Autodesk Fusion 360 part; units mm, degrees
(part 6 of 8)
equation "d503 = ( caseWidth - 20 mm ) - bottomBossDiameter / 2 - bottomReliefClearance"
equation "d504 = ( ( ( caseWidth - 20 mm ) - bottomBossDiameter / 2 - bottomReliefClearance ) + ( bottomBossDiameter + 2 * bottomReliefClearance ) ) - ( ( caseWidth - 20 mm ) - bottomBossDiameter / 2 - bottomReliefClearance )"
equation "d505 = ( ( 0 mm ) + ( 4.8 mm + bottomBossDiameter / 2 + bottomReliefClearance ) ) - ( 0 mm )"
equation "d506 = rearHeight + 1 mm"
equation "diffuserSkin = 0.8 mm" comment "Prototype optical front skin"
equation "diffuserSideWall = 1 mm" comment "Prototype hollow plug walls"
equation "diffuserRearDepth = 6 mm" comment "Rear rim presses strip edges"
equation "ledTrayDepth = 6.2 mm" comment "LED strip seat below exterior face"
equation "ledTrayThickness = 2.4 mm" comment "Structural LED tray"
equation "ledWireWidth = 4 mm" comment "Right-hand prototype wiring relief"
equation "oledBoardWidth = 36 mm" comment "Measured PCB orientation across case"
equation "oledBoardLength = 34 mm" comment "Measured PCB orientation along face"
equation "oledPcbThickness = 1.6 mm" comment "Confirmed OLED PCB thickness"
equation "oledPcbFrontDepth = 2.8 mm" comment "Provisional OLED PCB front seating depth"
equation "oledFitClearance = 0.2 mm" comment "Prototype PCB fit clearance"
equation "oledBackDepth = oledPcbFrontDepth + oledPcbThickness" comment "OLED PCB rear face"
equation "pcbPostDiameter = 4.4 mm" comment "Trial PCB screw support diameter"
equation "pcbPostHeight = pcbRailHeight + pcbRailThickness - pcbMountHeight" comment "Short PCB posts below control hardware"
equation "pcbPostPilot = 1.7 mm" comment "Trial M2 plastic thread pilot; coupon required"
equation "d523 = -( shellWall + diffuserFlangeThickness )"
equation "d525 = ( caseWidth - ledWidth ) / 2 + diffuserClearance - diffuserFlange"
equation "d526 = ( ledCenter - ledHeight / 2 + diffuserClearance - diffuserFlange ) + faceOriginV"
equation "d527 = ( ( ( caseWidth - ledWidth ) / 2 + diffuserClearance - diffuserFlange ) + ( ledWidth - 2 * diffuserClearance + 2 * diffuserFlange ) ) - ( ( caseWidth - ledWidth ) / 2 + diffuserClearance - diffuserFlange )"
equation "d528 = ( ( ( ledCenter - ledHeight / 2 + diffuserClearance - diffuserFlange ) + faceOriginV ) + ( ledHeight - 2 * diffuserClearance + 2 * diffuserFlange ) ) - ( ( ledCenter - ledHeight / 2 + diffuserClearance - diffuserFlange ) + faceOriginV )"
equation "d529 = -( diffuserRearDepth - shellWall - diffuserFlangeThickness )"
equation "d531 = -diffuserSkin"
equation "d533 = ( caseWidth - ledWidth ) / 2 + diffuserClearance + diffuserSideWall"
equation "d534 = ( ledCenter - ledHeight / 2 + diffuserClearance + diffuserSideWall ) + faceOriginV"
equation "d535 = ( ( ( caseWidth - ledWidth ) / 2 + diffuserClearance + diffuserSideWall ) + ( ledWidth - 2 * ( diffuserClearance + diffuserSideWall ) ) ) - ( ( caseWidth - ledWidth ) / 2 + diffuserClearance + diffuserSideWall )"
equation "d536 = ( ( ( ledCenter - ledHeight / 2 + diffuserClearance + diffuserSideWall ) + faceOriginV ) + ( ledHeight - 2 * ( diffuserClearance + diffuserSideWall ) ) ) - ( ( ledCenter - ledHeight / 2 + diffuserClearance + diffuserSideWall ) + faceOriginV )"
equation "d537 = -( diffuserRearDepth + 1 mm )"
equation "d539 = ( caseWidth + ledWidth ) / 2 - diffuserSideWall - 1 mm"
equation "d540 = ( ledCenter - ledWireWidth / 2 ) + faceOriginV"
equation "d541 = ( ( ( caseWidth + ledWidth ) / 2 - diffuserSideWall - 1 mm ) + ( 5 mm ) ) - ( ( caseWidth + ledWidth ) / 2 - diffuserSideWall - 1 mm )"
equation "d542 = ( ( ( ledCenter - ledWireWidth / 2 ) + faceOriginV ) + ( ledWireWidth ) ) - ( ( ledCenter - ledWireWidth / 2 ) + faceOriginV )"
equation "d543 = -( diffuserRearDepth )"
equation "d545 = ( caseWidth - ledWidth ) / 2 + diffuserClearance - diffuserFlange - flangePocketClearance"
equation "d546 = ( ledCenter - ledHeight / 2 + diffuserClearance - diffuserFlange - flangePocketClearance ) + faceOriginV"
equation "d547 = ( ( ( caseWidth - ledWidth ) / 2 + diffuserClearance - diffuserFlange - flangePocketClearance ) + ( ledWidth - 2 * diffuserClearance + 2 * ( diffuserFlange + flangePocketClearance ) ) ) - ( ( caseWidth - ledWidth ) / 2 + diffuserClearance - diffuserFlange - flangePocketClearance )"
equation "d548 = ( ( ( ledCenter - ledHeight / 2 + diffuserClearance - diffuserFlange - flangePocketClearance ) + faceOriginV ) + ( ledHeight - 2 * diffuserClearance + 2 * ( diffuserFlange + flangePocketClearance ) ) ) - ( ( ledCenter - ledHeight / 2 + diffuserClearance - diffuserFlange - flangePocketClearance ) + faceOriginV )"
equation "d549 = -( diffuserRearDepth - shellWall - carrierClearance + 0.2 mm )"
equation "d551 = ( caseWidth - ledWidth ) / 2 - 0.2 mm"
equation "d552 = ( faceLength - ( shellWall + carrierClearance ) / cos(caseTilt) - ( shellWall + carrierClearance + carrierThickness ) * tan(caseTilt) - carrierRim + 0.4 mm ) + faceOriginV"
equation "d553 = ( ( ( caseWidth - ledWidth ) / 2 - 0.2 mm ) + ( ledWidth + 0.4 mm ) ) - ( ( caseWidth - ledWidth ) / 2 - 0.2 mm )"
equation "d554 = ( ( ( faceLength - ( shellWall + carrierClearance ) / cos(caseTilt) - ( shellWall + carrierClearance + carrierThickness ) * tan(caseTilt) - carrierRim + 0.4 mm ) + faceOriginV ) + ( 4 mm ) ) - ( ( faceLength - ( shellWall + carrierClearance ) / cos(caseTilt) - ( shellWall + carrierClearance + carrierThickness ) * tan(caseTilt) - carrierRim + 0.4 mm ) + faceOriginV )"
equation "d555 = -( ledTrayDepth + ledTrayThickness - shellWall - carrierClearance )"
equation "d557 = -ledTrayDepth"
equation "d559 = ( caseWidth - ledWidth ) / 2 - 0.2 mm"
equation "d560 = ( ledCenter - ledHeight / 2 - 0.2 mm ) + faceOriginV"
equation "d561 = ( ( ( caseWidth - ledWidth ) / 2 - 0.2 mm ) + ( ledWidth + 0.4 mm ) ) - ( ( caseWidth - ledWidth ) / 2 - 0.2 mm )"
equation "d562 = ( ( ( ledCenter - ledHeight / 2 - 0.2 mm ) + faceOriginV ) + ( ( faceLength - ( shellWall + carrierClearance ) / cos(caseTilt) - ( ledTrayDepth + ledTrayThickness ) * tan(caseTilt) ) - ( ledCenter - ledHeight / 2 - 0.2 mm ) ) ) - ( ( ledCenter - ledHeight / 2 - 0.2 mm ) + faceOriginV )"
equation "d563 = -( ledTrayThickness )"
equation "d565 = ( caseWidth + ledWidth ) / 2 - 2 mm"
equation "d566 = ( ledCenter - ledWireWidth / 2 ) + faceOriginV"
equation "d567 = ( ( ( caseWidth + ledWidth ) / 2 - 2 mm ) + ( 4 mm ) ) - ( ( caseWidth + ledWidth ) / 2 - 2 mm )"
equation "d568 = ( ( ( ledCenter - ledWireWidth / 2 ) + faceOriginV ) + ( ledWireWidth ) ) - ( ( ledCenter - ledWireWidth / 2 ) + faceOriginV )"
equation "d569 = -( ledTrayThickness + 1 mm )"
equation "d571 = layoutGap + ( displayWidth - oledBoardWidth ) / 2"
equation "d572 = ( controlCenter - oledBoardLength / 2 ) + faceOriginV"
equation "d573 = ( ( layoutGap + ( displayWidth - oledBoardWidth ) / 2 ) + ( oledBoardWidth ) ) - ( layoutGap + ( displayWidth - oledBoardWidth ) / 2 )"
equation "d574 = ( ( ( controlCenter - oledBoardLength / 2 ) + faceOriginV ) + ( 3 mm ) ) - ( ( controlCenter - oledBoardLength / 2 ) + faceOriginV )"
equation "d575 = -( oledPcbFrontDepth )"
equation "d577 = layoutGap + ( displayWidth - oledBoardWidth ) / 2"
equation "d578 = ( controlCenter + oledBoardLength / 2 - 5 mm ) + faceOriginV"
equation "d579 = ( ( layoutGap + ( displayWidth - oledBoardWidth ) / 2 ) + ( oledBoardWidth ) ) - ( layoutGap + ( displayWidth - oledBoardWidth ) / 2 )"
equation "d580 = ( ( ( controlCenter + oledBoardLength / 2 - 5 mm ) + faceOriginV ) + ( 3 mm ) ) - ( ( controlCenter + oledBoardLength / 2 - 5 mm ) + faceOriginV )"
equation "d581 = -( oledPcbFrontDepth )"
equation "d583 = layoutGap + ( displayWidth - oledBoardWidth ) / 2 - oledFitClearance"
equation "d584 = ( controlCenter - oledBoardLength / 2 - oledFitClearance ) + faceOriginV"
equation "d585 = ( ( layoutGap + ( displayWidth - oledBoardWidth ) / 2 - oledFitClearance ) + ( oledBoardWidth + 2 * oledFitClearance ) ) - ( layoutGap + ( displayWidth - oledBoardWidth ) / 2 - oledFitClearance )"
equation "d586 = ( ( ( controlCenter - oledBoardLength / 2 - oledFitClearance ) + faceOriginV ) + ( oledBoardLength + 2 * oledFitClearance ) ) - ( ( controlCenter - oledBoardLength / 2 - oledFitClearance ) + faceOriginV )"
equation "d587 = -( oledBackDepth + oledFitClearance - shellWall - carrierClearance )"
equation "d589 = -( oledBackDepth + oledFitClearance )"
equation "d592 = ( controlCenter - 18 mm ) + faceOriginV"
equation "d593 = ( ( 18 mm ) + ( 14 mm ) ) - ( 18 mm )"
equation "d594 = ( ( ( controlCenter - 18 mm ) + faceOriginV ) + ( 1 mm ) ) - ( ( controlCenter - 18 mm ) + faceOriginV )"
equation "d595 = -( oledBackDepth + oledFitClearance + 2 mm - shellWall - carrierClearance )"
equation "d598 = ( controlCenter - 18 mm ) + faceOriginV"
equation "d599 = ( ( 18 mm ) + ( 14 mm ) ) - ( 18 mm )"
equation "d600 = ( ( ( controlCenter - 18 mm ) + faceOriginV ) + ( 4 mm ) ) - ( ( controlCenter - 18 mm ) + faceOriginV )"
equation "d601 = -( 2 mm )"
equation "d604 = ( controlCenter + 12.8 mm ) + faceOriginV"
equation "d605 = ( ( 18 mm ) + ( 14 mm ) ) - ( 18 mm )"
equation "d606 = ( ( ( controlCenter + 12.8 mm ) + faceOriginV ) + ( 3.8 mm ) ) - ( ( controlCenter + 12.8 mm ) + faceOriginV )"
equation "d607 = -( ledTrayThickness )"
equation "d610 = ( controlCenter + 13 mm ) + faceOriginV"
equation "d611 = ( ( 18 mm ) + ( 14 mm ) ) - ( 18 mm )"
equation "d612 = ( ( ( controlCenter + 13 mm ) + faceOriginV ) + ( 2 mm ) ) - ( ( controlCenter + 13 mm ) + faceOriginV )"
equation "d613 = -( 2 mm )"
equation "d615 = layoutGap + ( displayWidth - oledBoardWidth ) / 2 - oledFitClearance"
equation "d616 = ( controlCenter - oledBoardLength / 2 - oledFitClearance ) + faceOriginV"
equation "d617 = ( ( layoutGap + ( displayWidth - oledBoardWidth ) / 2 - oledFitClearance ) + ( oledBoardWidth + 2 * oledFitClearance ) ) - ( layoutGap + ( displayWidth - oledBoardWidth ) / 2 - oledFitClearance )"
equation "d618 = ( ( ( controlCenter - oledBoardLength / 2 - oledFitClearance ) + faceOriginV ) + ( oledBoardLength + 2 * oledFitClearance ) ) - ( ( controlCenter - oledBoardLength / 2 - oledFitClearance ) + faceOriginV )"
equation "d619 = -( oledBackDepth + oledFitClearance - shellWall - carrierClearance )"
equation "d621 = pcbTopHeight + 4 mm"
equation "d624 = ( pcbFront + ( pcbLength - pcbHolePitchY ) / 2 + 0 * pcbHolePitchY ) - 2 mm"
equation "d625 = ( ( 3.2 mm ) + ( 1.6 mm ) ) - ( 3.2 mm )"
equation "d626 = ( ( ( pcbFront + ( pcbLength - pcbHolePitchY ) / 2 + 0 * pcbHolePitchY ) - 2 mm ) + ( 4 mm ) ) - ( ( pcbFront + ( pcbLength - pcbHolePitchY ) / 2 + 0 * pcbHolePitchY ) - 2 mm )"
equation "d630 = ( pcbFront + ( pcbLength - pcbHolePitchY ) / 2 + 0 * pcbHolePitchY ) - 2 mm"
equation "d631 = ( ( 3.2 mm ) + ( 3.8 mm ) ) - ( 3.2 mm )"
equation "d632 = ( ( ( pcbFront + ( pcbLength - pcbHolePitchY ) / 2 + 0 * pcbHolePitchY ) - 2 mm ) + ( 4 mm ) ) - ( ( pcbFront + ( pcbLength - pcbHolePitchY ) / 2 + 0 * pcbHolePitchY ) - 2 mm )"
equation "d635 = pcbLeft + ( pcbWidth - pcbHolePitchX ) / 2 + 0 * pcbHolePitchX"
equation "d636 = pcbFront + ( pcbLength - pcbHolePitchY ) / 2 + 0 * pcbHolePitchY"
equation "d637 = pcbPostDiameter"
equation "d640 = pcbLeft + ( pcbWidth - pcbHolePitchX ) / 2 + 0 * pcbHolePitchX"
equation "d641 = pcbFront + ( pcbLength - pcbHolePitchY ) / 2 + 0 * pcbHolePitchY"
equation "d642 = pcbPostPilot"
equation "d645 = caseWidth - 4.8 mm"
equation "d646 = ( pcbFront + ( pcbLength - pcbHolePitchY ) / 2 + 0 * pcbHolePitchY ) - 2 mm"
equation "d647 = ( ( caseWidth - 4.8 mm ) + ( 1.6 mm ) ) - ( caseWidth - 4.8 mm )"
equation "d648 = ( ( ( pcbFront + ( pcbLength - pcbHolePitchY ) / 2 + 0 * pcbHolePitchY ) - 2 mm ) + ( 4 mm ) ) - ( ( pcbFront + ( pcbLength - pcbHolePitchY ) / 2 + 0 * pcbHolePitchY ) - 2 mm )"
equation "d651 = caseWidth - 7 mm"
equation "d652 = ( pcbFront + ( pcbLength - pcbHolePitchY ) / 2 + 0 * pcbHolePitchY ) - 2 mm"
equation "d653 = ( ( caseWidth - 7 mm ) + ( 3.8 mm ) ) - ( caseWidth - 7 mm )"
equation "d654 = ( ( ( pcbFront + ( pcbLength - pcbHolePitchY ) / 2 + 0 * pcbHolePitchY ) - 2 mm ) + ( 4 mm ) ) - ( ( pcbFront + ( pcbLength - pcbHolePitchY ) / 2 + 0 * pcbHolePitchY ) - 2 mm )"
equation "d657 = pcbLeft + ( pcbWidth - pcbHolePitchX ) / 2 + 1 * pcbHolePitchX"
equation "d658 = pcbFront + ( pcbLength - pcbHolePitchY ) / 2 + 0 * pcbHolePitchY"
equation "d659 = pcbPostDiameter"
equation "d662 = pcbLeft + ( pcbWidth - pcbHolePitchX ) / 2 + 1 * pcbHolePitchX"
equation "d663 = pcbFront + ( pcbLength - pcbHolePitchY ) / 2 + 0 * pcbHolePitchY"
equation "d664 = pcbPostPilot"
equation "d668 = ( pcbFront + ( pcbLength - pcbHolePitchY ) / 2 + 1 * pcbHolePitchY ) - 2 mm"
equation "d669 = ( ( 3.2 mm ) + ( 1.6 mm ) ) - ( 3.2 mm )"
equation "d670 = ( ( ( pcbFront + ( pcbLength - pcbHolePitchY ) / 2 + 1 * pcbHolePitchY ) - 2 mm ) + ( 4 mm ) ) - ( ( pcbFront + ( pcbLength - pcbHolePitchY ) / 2 + 1 * pcbHolePitchY ) - 2 mm )"
equation "d674 = ( pcbFront + ( pcbLength - pcbHolePitchY ) / 2 + 1 * pcbHolePitchY ) - 2 mm"
equation "d675 = ( ( 3.2 mm ) + ( 3.8 mm ) ) - ( 3.2 mm )"
equation "d676 = ( ( ( pcbFront + ( pcbLength - pcbHolePitchY ) / 2 + 1 * pcbHolePitchY ) - 2 mm ) + ( 4 mm ) ) - ( ( pcbFront + ( pcbLength - pcbHolePitchY ) / 2 + 1 * pcbHolePitchY ) - 2 mm )"
equation "d679 = pcbLeft + ( pcbWidth - pcbHolePitchX ) / 2 + 0 * pcbHolePitchX"
equation "d680 = pcbFront + ( pcbLength - pcbHolePitchY ) / 2 + 1 * pcbHolePitchY"
equation "d681 = pcbPostDiameter"
equation "d684 = pcbLeft + ( pcbWidth - pcbHolePitchX ) / 2 + 0 * pcbHolePitchX"
equation "d685 = pcbFront + ( pcbLength - pcbHolePitchY ) / 2 + 1 * pcbHolePitchY"
equation "d686 = pcbPostPilot"
equation "d689 = caseWidth - 4.8 mm"
equation "d690 = ( pcbFront + ( pcbLength - pcbHolePitchY ) / 2 + 1 * pcbHolePitchY ) - 2 mm"
equation "d691 = ( ( caseWidth - 4.8 mm ) + ( 1.6 mm ) ) - ( caseWidth - 4.8 mm )"
equation "d692 = ( ( ( pcbFront + ( pcbLength - pcbHolePitchY ) / 2 + 1 * pcbHolePitchY ) - 2 mm ) + ( 4 mm ) ) - ( ( pcbFront + ( pcbLength - pcbHolePitchY ) / 2 + 1 * pcbHolePitchY ) - 2 mm )"
equation "d695 = caseWidth - 7 mm"
equation "d696 = ( pcbFront + ( pcbLength - pcbHolePitchY ) / 2 + 1 * pcbHolePitchY ) - 2 mm"
equation "d697 = ( ( caseWidth - 7 mm ) + ( 3.8 mm ) ) - ( caseWidth - 7 mm )"
equation "d698 = ( ( ( pcbFront + ( pcbLength - pcbHolePitchY ) / 2 + 1 * pcbHolePitchY ) - 2 mm ) + ( 4 mm ) ) - ( ( pcbFront + ( pcbLength - pcbHolePitchY ) / 2 + 1 * pcbHolePitchY ) - 2 mm )"
equation "d701 = pcbLeft + ( pcbWidth - pcbHolePitchX ) / 2 + 1 * pcbHolePitchX"
equation "d702 = pcbFront + ( pcbLength - pcbHolePitchY ) / 2 + 1 * pcbHolePitchY"
equation "d703 = pcbPostDiameter"
equation "d706 = pcbLeft + ( pcbWidth - pcbHolePitchX ) / 2 + 1 * pcbHolePitchX"
equation "d707 = pcbFront + ( pcbLength - pcbHolePitchY ) / 2 + 1 * pcbHolePitchY"
equation "d708 = pcbPostPilot"
equation "d711 = -( carrierBossDepth + carrierClearance )"
equation "d713 = mountSideX"
equation "d714 = ( mountFrontV ) + faceOriginV"
equation "d715 = mountBossDiameter"
equation "d716 = -( carrierClearance )"
equation "d718 = mountSideX"
equation "d719 = ( mountFrontV ) + faceOriginV"
equation "d720 = insertPilotDiameter"
equation "d721 = carrierClearance + 0.1 mm"
equation "d723 = caseWidth - mountSideX"
equation "d724 = ( mountFrontV ) + faceOriginV"
equation "d725 = mountBossDiameter"
equation "d726 = -( carrierClearance )"
equation "d728 = caseWidth - mountSideX"
equation "d729 = ( mountFrontV ) + faceOriginV"
equation "d730 = insertPilotDiameter"
equation "d731 = carrierClearance + 0.1 mm"
equation "d733 = mountSideX"
equation "d734 = ( mountRearV ) + faceOriginV"
equation "d735 = mountBossDiameter"
equation "d736 = -( carrierClearance )"
equation "d738 = mountSideX"
equation "d739 = ( mountRearV ) + faceOriginV"
equation "d740 = insertPilotDiameter"
equation "d741 = carrierClearance + 0.1 mm"
equation "d743 = mountSideX"
equation "d744 = ( mountRearV ) + faceOriginV"
equation "d745 = mountBossDiameter + 2 * mountPocketClearance"
equation "d746 = carrierBossDepth + carrierClearance"
equation "d748 = mountSideX"
equation "d749 = ( mountRearV ) + faceOriginV"
equation "d750 = m2Clearance"
equation "d751 = -( carrierPadDepth )"
equation "d754 = caseLength - 3 mm"
equation "d755 = bottomBossDiameter + 2 * bottomReliefClearance"
equation "d756 = rearHeight + 1 mm"
equation "d758 = caseWidth - mountSideX"
equation "d759 = ( mountRearV ) + faceOriginV"
equation "d760 = mountBossDiameter"
equation "d761 = -( carrierClearance )"
equation "d763 = caseWidth - mountSideX"
equation "d764 = ( mountRearV ) + faceOriginV"
equation "d765 = insertPilotDiameter"
equation "d766 = carrierClearance + 0.1 mm"
equation "d768 = caseWidth - mountSideX"
equation "d769 = ( mountRearV ) + faceOriginV"
equation "d770 = mountBossDiameter + 2 * mountPocketClearance"
equation "d771 = carrierBossDepth + carrierClearance"
equation "d773 = caseWidth - mountSideX"
equation "d774 = ( mountRearV ) + faceOriginV"
equation "d775 = m2Clearance"
equation "d776 = -( carrierPadDepth )"
equation "d778 = caseWidth - 20 mm"
equation "d779 = caseLength - 3 mm"
equation "d780 = bottomBossDiameter + 2 * bottomReliefClearance"
equation "d781 = rearHeight + 1 mm"
equation "pcbMountHeight = 22.3 mm" comment "Upper solder-side PCB seating face; components face bottom cover"
equation "pcbRailHeight = 27.8 mm" comment "Short screw bosses attach to continuous outer carrier rails"
equation "pcbRailThickness = 1.5 mm" comment "Mounting ear thickness"
equation "d788 = -( ( 0 ) * ( pcbFront ) + ( -1 ) * ( pcbRailHeight ) )"
equation "d789 = ( 1 ) * ( pcbFront ) + ( 0 ) * ( pcbRailHeight )"
equation "d790 = ( ( 1 ) * ( pcbRear ) + ( 0 ) * ( pcbRailHeight ) ) - ( ( 1 ) * ( pcbFront ) + ( 0 ) * ( pcbRailHeight ) )"
equation "d791 = -( ( ( 0 ) * ( pcbRear ) + ( -1 ) * ( frontHeight + pcbRear * tan(caseTilt) - ( shellWall + carrierClearance + carrierThickness - 0.3 mm ) / cos(caseTilt) ) ) - ( ( 0 ) * ( pcbRear ) + ( -1 ) * ( pcbRailHeight ) ) )"
equation "d792 = ( ( 0 ) * ( pcbFront ) + ( -1 ) * ( pcbRailHeight ) ) - ( ( 0 ) * ( pcbFront ) + ( -1 ) * ( frontHeight + pcbFront * tan(caseTilt) - ( shellWall + carrierClearance + carrierThickness - 0.3 mm ) / cos(caseTilt) ) )"
equation "d795 = caseWidth - 4.8 mm"
equation "d797 = -( ( 0 ) * ( pcbFront ) + ( -1 ) * ( pcbRailHeight ) )"
equation "d798 = ( 1 ) * ( pcbFront ) + ( 0 ) * ( pcbRailHeight )"
equation "d799 = ( ( 1 ) * ( pcbRear ) + ( 0 ) * ( pcbRailHeight ) ) - ( ( 1 ) * ( pcbFront ) + ( 0 ) * ( pcbRailHeight ) )"
equation "d800 = -( ( ( 0 ) * ( pcbRear ) + ( -1 ) * ( frontHeight + pcbRear * tan(caseTilt) - ( shellWall + carrierClearance + carrierThickness - 0.3 mm ) / cos(caseTilt) ) ) - ( ( 0 ) * ( pcbRear ) + ( -1 ) * ( pcbRailHeight ) ) )"
equation "d801 = ( ( 0 ) * ( pcbFront ) + ( -1 ) * ( pcbRailHeight ) ) - ( ( 0 ) * ( pcbFront ) + ( -1 ) * ( frontHeight + pcbFront * tan(caseTilt) - ( shellWall + carrierClearance + carrierThickness - 0.3 mm ) / cos(caseTilt) ) )"
equation "d804 = pcbRailHeight"
equation "d807 = ( pcbFront + ( pcbLength - pcbHolePitchY ) / 2 + 0 * pcbHolePitchY ) - 2.2 mm"
equation "d808 = ( ( 3.2 mm ) + ( 6 mm ) ) - ( 3.2 mm )"
equation "d809 = ( ( ( pcbFront + ( pcbLength - pcbHolePitchY ) / 2 + 0 * pcbHolePitchY ) - 2.2 mm ) + ( 4.4 mm ) ) - ( ( pcbFront + ( pcbLength - pcbHolePitchY ) / 2 + 0 * pcbHolePitchY ) - 2.2 mm )"
equation "d810 = pcbRailThickness"
equation "d812 = pcbLeft + ( pcbWidth - pcbHolePitchX ) / 2 + 0 * pcbHolePitchX"
equation "d813 = pcbFront + ( pcbLength - pcbHolePitchY ) / 2 + 0 * pcbHolePitchY"
equation "d814 = pcbPostDiameter"
equation "d815 = pcbPostHeight"
equation "d817 = pcbLeft + ( pcbWidth - pcbHolePitchX ) / 2 + 0 * pcbHolePitchX"
equation "d818 = pcbFront + ( pcbLength - pcbHolePitchY ) / 2 + 0 * pcbHolePitchY"
equation "d819 = pcbPostPilot"
equation "d822 = caseWidth - 9.2 mm"
equation "d823 = ( pcbFront + ( pcbLength - pcbHolePitchY ) / 2 + 0 * pcbHolePitchY ) - 2.2 mm"
equation "d824 = ( ( caseWidth - 9.2 mm ) + ( 6 mm ) ) - ( caseWidth - 9.2 mm )"
equation "d825 = ( ( ( pcbFront + ( pcbLength - pcbHolePitchY ) / 2 + 0 * pcbHolePitchY ) - 2.2 mm ) + ( 4.4 mm ) ) - ( ( pcbFront + ( pcbLength - pcbHolePitchY ) / 2 + 0 * pcbHolePitchY ) - 2.2 mm )"
equation "d826 = pcbRailThickness"
equation "d828 = pcbLeft + ( pcbWidth - pcbHolePitchX ) / 2 + 1 * pcbHolePitchX"
equation "d829 = pcbFront + ( pcbLength - pcbHolePitchY ) / 2 + 0 * pcbHolePitchY"
equation "d830 = pcbPostDiameter"
equation "d831 = pcbPostHeight"
equation "d833 = pcbLeft + ( pcbWidth - pcbHolePitchX ) / 2 + 1 * pcbHolePitchX"
equation "d834 = pcbFront + ( pcbLength - pcbHolePitchY ) / 2 + 0 * pcbHolePitchY"
equation "d835 = pcbPostPilot"
equation "d839 = ( pcbFront + ( pcbLength - pcbHolePitchY ) / 2 + 1 * pcbHolePitchY ) - 2.2 mm"
equation "d840 = ( ( 3.2 mm ) + ( 6 mm ) ) - ( 3.2 mm )"
equation "d841 = ( ( ( pcbFront + ( pcbLength - pcbHolePitchY ) / 2 + 1 * pcbHolePitchY ) - 2.2 mm ) + ( 4.4 mm ) ) - ( ( pcbFront + ( pcbLength - pcbHolePitchY ) / 2 + 1 * pcbHolePitchY ) - 2.2 mm )"
equation "d842 = pcbRailThickness"
equation "d844 = pcbLeft + ( pcbWidth - pcbHolePitchX ) / 2 + 0 * pcbHolePitchX"
equation "d845 = pcbFront + ( pcbLength - pcbHolePitchY ) / 2 + 1 * pcbHolePitchY"
equation "d846 = pcbPostDiameter"
equation "d847 = pcbPostHeight"
equation "d849 = pcbLeft + ( pcbWidth - pcbHolePitchX ) / 2 + 0 * pcbHolePitchX"
equation "d850 = pcbFront + ( pcbLength - pcbHolePitchY ) / 2 + 1 * pcbHolePitchY"
equation "d851 = pcbPostPilot"
equation "d854 = caseWidth - 9.2 mm"
equation "d855 = ( pcbFront + ( pcbLength - pcbHolePitchY ) / 2 + 1 * pcbHolePitchY ) - 2.2 mm"
equation "d856 = ( ( caseWidth - 9.2 mm ) + ( 6 mm ) ) - ( caseWidth - 9.2 mm )"
equation "d857 = ( ( ( pcbFront + ( pcbLength - pcbHolePitchY ) / 2 + 1 * pcbHolePitchY ) - 2.2 mm ) + ( 4.4 mm ) ) - ( ( pcbFront + ( pcbLength - pcbHolePitchY ) / 2 + 1 * pcbHolePitchY ) - 2.2 mm )"
equation "d858 = pcbRailThickness"
equation "d860 = pcbLeft + ( pcbWidth - pcbHolePitchX ) / 2 + 1 * pcbHolePitchX"
equation "d861 = pcbFront + ( pcbLength - pcbHolePitchY ) / 2 + 1 * pcbHolePitchY"
equation "d862 = pcbPostDiameter"
equation "d863 = pcbPostHeight"
equation "d865 = pcbLeft + ( pcbWidth - pcbHolePitchX ) / 2 + 1 * pcbHolePitchX"
equation "d866 = pcbFront + ( pcbLength - pcbHolePitchY ) / 2 + 1 * pcbHolePitchY"
equation "d867 = pcbPostPilot"
equation "holderStemX = -0.08972306 mm" comment "Fitted central cylinder X in original holder mesh"
equation "holderStemY = 1.49765268 mm" comment "Fitted central cylinder Y in original holder mesh"
equation "holderWidth = 11.03147984 mm" comment "Exact 3MF X bounding width"
equation "holderLength = 9.74910164 mm" comment "Exact 3MF Y bounding length"
equation "holderHeight = 5.2 mm" comment "Exact 3MF bounding height"
equation "holderTopDepth = shellWall + carrierClearance + 7 mm" comment "Measured flange underside to holder top"
equation "holderBottomDepth = holderTopDepth + holderHeight" comment "Holder lower bearing plane"
equation "holderFit = 0.2 mm" comment "Provisional XY pocket clearance per side"
equation "holderFrameX = 18.4 mm" comment "Receiver outer width"
equation "holderFrameY = 17.6 mm" comment "Receiver outer length preserving OLED clearance"
equation "holderSwitchVoid = 16 mm" comment "Provisional switch lower-body clearance"
equation "holderHookOverlap = 0.3 mm" comment "Prototype retention overlap"
equation "holderHookThickness = 0.8 mm" comment "Snap retaining lip thickness"
equation "holderSpringWidth = 2 mm" comment "External spring width"
equation "holderSpringY = 3.7 mm" comment "Mesh-verified plastic edge band clear of contact exits"
equation "holderLidGap = 0.2 mm" comment "Normal clearance between holder underside and lid support"
equation "d1834 = -( shellWall + carrierClearance + carrierThickness )"
equation "d1836 = -holderTopDepth"
equation "d1838 = -holderBottomDepth"
equation "d1840 = -( shellWall + carrierClearance + carrierThickness + 1 mm )"
equation "d1842 = -( holderBottomDepth + holderLidGap )"
equation "d1844 = bottomThickness"
equation "d1846 = ( layoutGap + keycapSize / 2 + 0 * keyPitch ) - holderFrameX / 2"
equation "d1847 = ( ( keyRowOne ) - holderFrameY / 2 ) + faceOriginV"
equation "d1848 = ( ( ( layoutGap + keycapSize / 2 + 0 * keyPitch ) - holderFrameX / 2 ) + ( holderFrameX ) ) - ( ( layoutGap + keycapSize / 2 + 0 * keyPitch ) - holderFrameX / 2 )"
equation "d1849 = ( ( ( ( keyRowOne ) - holderFrameY / 2 ) + faceOriginV ) + ( holderFrameY ) ) - ( ( ( keyRowOne ) - holderFrameY / 2 ) + faceOriginV )"
equation "d1850 = -( holderBottomDepth + holderHookThickness - shellWall - carrierClearance - carrierThickness )"
equation "d1852 = ( layoutGap + keycapSize / 2 + 0 * keyPitch ) - holderSwitchVoid / 2"
equation "d1853 = ( ( keyRowOne ) - holderSwitchVoid / 2 ) + faceOriginV"
equation "d1854 = ( ( ( layoutGap + keycapSize / 2 + 0 * keyPitch ) - holderSwitchVoid / 2 ) + ( holderSwitchVoid ) ) - ( ( layoutGap + keycapSize / 2 + 0 * keyPitch ) - holderSwitchVoid / 2 )"
equation "d1855 = ( ( ( ( keyRowOne ) - holderSwitchVoid / 2 ) + faceOriginV ) + ( holderSwitchVoid ) ) - ( ( ( keyRowOne ) - holderSwitchVoid / 2 ) + faceOriginV )"
equation "d1856 = -( holderTopDepth - shellWall - carrierClearance - carrierThickness )"
equation "d1858 = ( ( layoutGap + keycapSize / 2 + 0 * keyPitch ) - holderStemX ) - holderWidth / 2 - holderFit"
equation "d1859 = ( ( ( keyRowOne ) - holderStemY ) - holderLength / 2 - holderFit ) + faceOriginV"
equation "d1860 = ( ( ( ( layoutGap + keycapSize / 2 + 0 * keyPitch ) - holderStemX ) - holderWidth / 2 - holderFit ) + ( holderWidth + 2 * holderFit ) ) - ( ( ( layoutGap + keycapSize / 2 + 0 * keyPitch ) - holderStemX ) - holderWidth / 2 - holderFit )"
equation "d1861 = ( ( ( ( ( keyRowOne ) - holderStemY ) - holderLength / 2 - holderFit ) + faceOriginV ) + ( holderLength + 2 * holderFit ) ) - ( ( ( ( keyRowOne ) - holderStemY ) - holderLength / 2 - holderFit ) + faceOriginV )"
equation "d1862 = -( holderHeight + holderHookThickness + 0.2 mm )"
equation "d1864 = ( ( layoutGap + keycapSize / 2 + 0 * keyPitch ) - holderStemX ) - holderFrameX / 2 - 0.1 mm"
equation "d1865 = ( ( ( ( keyRowOne ) - holderStemY ) + holderSpringY ) - holderSpringWidth / 2 - 0.6 mm ) + faceOriginV"
equation "d1866 = ( ( ( ( layoutGap + keycapSize / 2 + 0 * keyPitch ) - holderStemX ) - holderFrameX / 2 - 0.1 mm ) + ( holderFrameX / 2 - holderWidth / 2 - holderFit + 0.1 mm ) ) - ( ( ( layoutGap + keycapSize / 2 + 0 * keyPitch ) - holderStemX ) - holderFrameX / 2 - 0.1 mm )"
equation "d1867 = ( ( ( ( ( ( keyRowOne ) - holderStemY ) + holderSpringY ) - holderSpringWidth / 2 - 0.6 mm ) + faceOriginV ) + ( 0.6 mm ) ) - ( ( ( ( ( keyRowOne ) - holderStemY ) + holderSpringY ) - holderSpringWidth / 2 - 0.6 mm ) + faceOriginV )"
equation "d1868 = -( holderBottomDepth + holderHookThickness - shellWall - carrierClearance - carrierThickness - 1 mm + 0.2 mm )"
equation "d1870 = ( ( layoutGap + keycapSize / 2 + 0 * keyPitch ) - holderStemX ) - holderFrameX / 2 - 0.1 mm"
equation "d1871 = ( ( ( ( keyRowOne ) - holderStemY ) + holderSpringY ) + holderSpringWidth / 2 ) + faceOriginV"
equation "d1872 = ( ( ( ( layoutGap + keycapSize / 2 + 0 * keyPitch ) - holderStemX ) - holderFrameX / 2 - 0.1 mm ) + ( holderFrameX / 2 - holderWidth / 2 - holderFit + 0.1 mm ) ) - ( ( ( layoutGap + keycapSize / 2 + 0 * keyPitch ) - holderStemX ) - holderFrameX / 2 - 0.1 mm )"
equation "d1873 = ( ( ( ( ( ( keyRowOne ) - holderStemY ) + holderSpringY ) + holderSpringWidth / 2 ) + faceOriginV ) + ( 0.6 mm ) ) - ( ( ( ( ( keyRowOne ) - holderStemY ) + holderSpringY ) + holderSpringWidth / 2 ) + faceOriginV )"
equation "d1874 = -( holderBottomDepth + holderHookThickness - shellWall - carrierClearance - carrierThickness - 1 mm + 0.2 mm )"
equation "d1876 = ( ( layoutGap + keycapSize / 2 + 0 * keyPitch ) - holderStemX ) - holderFrameX / 2 + 0.8 mm"
equation "d1877 = ( ( ( ( keyRowOne ) - holderStemY ) + holderSpringY ) - holderSpringWidth / 2 ) + faceOriginV"
equation "d1878 = ( ( ( ( layoutGap + keycapSize / 2 + 0 * keyPitch ) - holderStemX ) - holderFrameX / 2 + 0.8 mm ) + ( holderFrameX / 2 - 0.8 mm - holderWidth / 2 - holderFit ) ) - ( ( ( layoutGap + keycapSize / 2 + 0 * keyPitch ) - holderStemX ) - holderFrameX / 2 + 0.8 mm )"
equation "d1879 = ( ( ( ( ( ( keyRowOne ) - holderStemY ) + holderSpringY ) - holderSpringWidth / 2 ) + faceOriginV ) + ( holderSpringWidth ) ) - ( ( ( ( ( keyRowOne ) - holderStemY ) + holderSpringY ) - holderSpringWidth / 2 ) + faceOriginV )"
equation "d1880 = -( holderHeight + holderHookThickness + 0.2 mm )"
equation "d1882 = ( ( layoutGap + keycapSize / 2 + 0 * keyPitch ) - holderStemX ) - holderFrameX / 2"
equation "d1883 = ( ( ( ( keyRowOne ) - holderStemY ) + holderSpringY ) - holderSpringWidth / 2 ) + faceOriginV"
equation "d1884 = ( ( ( ( layoutGap + keycapSize / 2 + 0 * keyPitch ) - holderStemX ) - holderFrameX / 2 ) + ( holderFrameX / 2 - holderWidth / 2 + holderHookOverlap ) ) - ( ( ( layoutGap + keycapSize / 2 + 0 * keyPitch ) - holderStemX ) - holderFrameX / 2 )"
equation "d1885 = ( ( ( ( ( ( keyRowOne ) - holderStemY ) + holderSpringY ) - holderSpringWidth / 2 ) + faceOriginV ) + ( holderSpringWidth ) ) - ( ( ( ( ( keyRowOne ) - holderStemY ) + holderSpringY ) - holderSpringWidth / 2 ) + faceOriginV )"
equation "d1886 = -( holderHookThickness )"
equation "d1889 = ( ( layoutGap + keycapSize / 2 + 0 * keyPitch ) - holderStemX ) + holderWidth / 2 + holderFit"
equation "d1890 = ( ( ( ( keyRowOne ) - holderStemY ) + holderSpringY ) - holderSpringWidth / 2 - 0.6 mm ) + faceOriginV"
equation "d1891 = ( ( ( ( layoutGap + keycapSize / 2 + 0 * keyPitch ) - holderStemX ) + holderWidth / 2 + holderFit ) + ( holderFrameX / 2 - holderWidth / 2 - holderFit + 0.1 mm ) ) - ( ( ( layoutGap + keycapSize / 2 + 0 * keyPitch ) - holderStemX ) + holderWidth / 2 + holderFit )"
equation "d1892 = ( ( ( ( ( ( keyRowOne ) - holderStemY ) + holderSpringY ) - holderSpringWidth / 2 - 0.6 mm ) + faceOriginV ) + ( 0.6 mm ) ) - ( ( ( ( ( keyRowOne ) - holderStemY ) + holderSpringY ) - holderSpringWidth / 2 - 0.6 mm ) + faceOriginV )"
equation "d1893 = -( holderBottomDepth + holderHookThickness - shellWall - carrierClearance - carrierThickness - 1 mm + 0.2 mm )"
equation "d1895 = ( ( layoutGap + keycapSize / 2 + 0 * keyPitch ) - holderStemX ) + holderWidth / 2 + holderFit"
equation "d1896 = ( ( ( ( keyRowOne ) - holderStemY ) + holderSpringY ) + holderSpringWidth / 2 ) + faceOriginV"
equation "d1897 = ( ( ( ( layoutGap + keycapSize / 2 + 0 * keyPitch ) - holderStemX ) + holderWidth / 2 + holderFit ) + ( holderFrameX / 2 - holderWidth / 2 - holderFit + 0.1 mm ) ) - ( ( ( layoutGap + keycapSize / 2 + 0 * keyPitch ) - holderStemX ) + holderWidth / 2 + holderFit )"
equation "d1898 = ( ( ( ( ( ( keyRowOne ) - holderStemY ) + holderSpringY ) + holderSpringWidth / 2 ) + faceOriginV ) + ( 0.6 mm ) ) - ( ( ( ( ( keyRowOne ) - holderStemY ) + holderSpringY ) + holderSpringWidth / 2 ) + faceOriginV )"
equation "d1899 = -( holderBottomDepth + holderHookThickness - shellWall - carrierClearance - carrierThickness - 1 mm + 0.2 mm )"
equation "d1901 = ( ( layoutGap + keycapSize / 2 + 0 * keyPitch ) - holderStemX ) + holderWidth / 2 + holderFit"
equation "d1902 = ( ( ( ( keyRowOne ) - holderStemY ) + holderSpringY ) - holderSpringWidth / 2 ) + faceOriginV"
equation "d1903 = ( ( ( ( layoutGap + keycapSize / 2 + 0 * keyPitch ) - holderStemX ) + holderWidth / 2 + holderFit ) + ( holderFrameX / 2 - 0.8 mm - holderWidth / 2 - holderFit ) ) - ( ( ( layoutGap + keycapSize / 2 + 0 * keyPitch ) - holderStemX ) + holderWidth / 2 + holderFit )"
equation "d1904 = ( ( ( ( ( ( keyRowOne ) - holderStemY ) + holderSpringY ) - holderSpringWidth / 2 ) + faceOriginV ) + ( holderSpringWidth ) ) - ( ( ( ( ( keyRowOne ) - holderStemY ) + holderSpringY ) - holderSpringWidth / 2 ) + faceOriginV )"
equation "d1905 = -( holderHeight + holderHookThickness + 0.2 mm )"
equation "d1907 = ( ( layoutGap + keycapSize / 2 + 0 * keyPitch ) - holderStemX ) + holderWidth / 2 - holderHookOverlap"
equation "d1908 = ( ( ( ( keyRowOne ) - holderStemY ) + holderSpringY ) - holderSpringWidth / 2 ) + faceOriginV"
equation "d1909 = ( ( ( ( layoutGap + keycapSize / 2 + 0 * keyPitch ) - holderStemX ) + holderWidth / 2 - holderHookOverlap ) + ( holderFrameX / 2 - holderWidth / 2 + holderHookOverlap ) ) - ( ( ( layoutGap + keycapSize / 2 + 0 * keyPitch ) - holderStemX ) + holderWidth / 2 - holderHookOverlap )"
equation "d1910 = ( ( ( ( ( ( keyRowOne ) - holderStemY ) + holderSpringY ) - holderSpringWidth / 2 ) + faceOriginV ) + ( holderSpringWidth ) ) - ( ( ( ( ( keyRowOne ) - holderStemY ) + holderSpringY ) - holderSpringWidth / 2 ) + faceOriginV )"
equation "d1911 = -( holderHookThickness )"
equation "d1914 = ( ( layoutGap + keycapSize / 2 + 0 * keyPitch ) - holderStemX ) + ( -3 mm ) - 0.5 mm"
equation "d1915 = ( ( ( keyRowOne ) - holderStemY ) + 4 mm ) + faceOriginV"
equation "d1916 = ( ( ( ( layoutGap + keycapSize / 2 + 0 * keyPitch ) - holderStemX ) + ( -3 mm ) - 0.5 mm ) + ( 1 mm ) ) - ( ( ( layoutGap + keycapSize / 2 + 0 * keyPitch ) - holderStemX ) + ( -3 mm ) - 0.5 mm )"
equation "d1917 = ( ( ( ( ( keyRowOne ) - holderStemY ) + 4 mm ) + faceOriginV ) + ( holderFrameY / 2 - 4 mm ) ) - ( ( ( ( keyRowOne ) - holderStemY ) + 4 mm ) + faceOriginV )"
equation "d1920 = ( ( layoutGap + keycapSize / 2 + 0 * keyPitch ) - holderStemX ) + ( 3 mm ) - 0.5 mm"
equation "d1921 = ( ( ( keyRowOne ) - holderStemY ) + 4 mm ) + faceOriginV"
equation "d1922 = ( ( ( ( layoutGap + keycapSize / 2 + 0 * keyPitch ) - holderStemX ) + ( 3 mm ) - 0.5 mm ) + ( 1 mm ) ) - ( ( ( layoutGap + keycapSize / 2 + 0 * keyPitch ) - holderStemX ) + ( 3 mm ) - 0.5 mm )"
equation "d1923 = ( ( ( ( ( keyRowOne ) - holderStemY ) + 4 mm ) + faceOriginV ) + ( holderFrameY / 2 - 4 mm ) ) - ( ( ( ( keyRowOne ) - holderStemY ) + 4 mm ) + faceOriginV )"
equation "d1928 = ( ( layoutGap + keycapSize / 2 + 0 * keyPitch ) - holderStemX ) - holderFrameX / 2 - 0.1 mm"
equation "d1929 = ( ( ( keyRowOne ) - holderStemY ) - 5.1 mm ) + faceOriginV"
equation "d1930 = ( ( ( ( layoutGap + keycapSize / 2 + 0 * keyPitch ) - holderStemX ) - holderFrameX / 2 - 0.1 mm ) + ( holderFrameX / 2 - holderWidth / 2 + 0.1 mm ) ) - ( ( ( layoutGap + keycapSize / 2 + 0 * keyPitch ) - holderStemX ) - holderFrameX / 2 - 0.1 mm )"
equation "d1931 = ( ( ( ( ( keyRowOne ) - holderStemY ) - 5.1 mm ) + faceOriginV ) + ( 7.8 mm ) ) - ( ( ( ( keyRowOne ) - holderStemY ) - 5.1 mm ) + faceOriginV )"
equation "d1932 = -( holderHeight + holderHookThickness - 1.2 mm + 0.2 mm )"
equation "d1934 = ( ( layoutGap + keycapSize / 2 + 0 * keyPitch ) - holderStemX ) + holderWidth / 2"
equation "d1935 = ( ( ( keyRowOne ) - holderStemY ) - 5.1 mm ) + faceOriginV"
equation "d1936 = ( ( ( ( layoutGap + keycapSize / 2 + 0 * keyPitch ) - holderStemX ) + holderWidth / 2 ) + ( holderFrameX / 2 - holderWidth / 2 + 0.1 mm ) ) - ( ( ( layoutGap + keycapSize / 2 + 0 * keyPitch ) - holderStemX ) + holderWidth / 2 )"
equation "d1937 = ( ( ( ( ( keyRowOne ) - holderStemY ) - 5.1 mm ) + faceOriginV ) + ( 7.8 mm ) ) - ( ( ( ( keyRowOne ) - holderStemY ) - 5.1 mm ) + faceOriginV )"
equation "d1938 = -( holderHeight + holderHookThickness - 1.2 mm + 0.2 mm )"
equation "d1940 = ( ( layoutGap + keycapSize / 2 + 0 * keyPitch ) - holderStemX ) + ( -2.5 mm ) - 1.2 mm"
equation "d1941 = ( ( ( ( keyRowOne ) - holderStemY ) - 1.2 mm ) * cos(caseTilt) + ( holderBottomDepth + holderLidGap ) * sin(caseTilt) ) - 2.5 mm"
equation "d1942 = ( ( ( ( layoutGap + keycapSize / 2 + 0 * keyPitch ) - holderStemX ) + ( -2.5 mm ) - 1.2 mm ) + ( 2.4 mm ) ) - ( ( ( layoutGap + keycapSize / 2 + 0 * keyPitch ) - holderStemX ) + ( -2.5 mm ) - 1.2 mm )"
equation "d1943 = ( ( ( ( ( ( keyRowOne ) - holderStemY ) - 1.2 mm ) * cos(caseTilt) + ( holderBottomDepth + holderLidGap ) * sin(caseTilt) ) - 2.5 mm ) + ( 5 mm ) ) - ( ( ( ( ( keyRowOne ) - holderStemY ) - 1.2 mm ) * cos(caseTilt) + ( holderBottomDepth + holderLidGap ) * sin(caseTilt) ) - 2.5 mm )"
equation "d1944 = ( frontHeight + ( ( ( keyRowOne ) - holderStemY ) - 1.2 mm ) * sin(caseTilt) - ( holderBottomDepth + holderLidGap ) * cos(caseTilt) ) - bottomThickness - 2 mm"
equation "d1946 = ( ( layoutGap + keycapSize / 2 + 0 * keyPitch ) - holderStemX ) + ( -2.5 mm ) - 0.5 mm"
equation "d1947 = ( ( ( ( keyRowOne ) - holderStemY ) - 1.2 mm ) * cos(caseTilt) + ( holderBottomDepth + holderLidGap ) * sin(caseTilt) ) - 1.5 mm"
equation "d1948 = ( ( ( ( layoutGap + keycapSize / 2 + 0 * keyPitch ) - holderStemX ) + ( -2.5 mm ) - 0.5 mm ) + ( 1 mm ) ) - ( ( ( layoutGap + keycapSize / 2 + 0 * keyPitch ) - holderStemX ) + ( -2.5 mm ) - 0.5 mm )"
equation "d1949 = ( ( ( ( ( ( keyRowOne ) - holderStemY ) - 1.2 mm ) * cos(caseTilt) + ( holderBottomDepth + holderLidGap ) * sin(caseTilt) ) - 1.5 mm ) + ( 3 mm ) ) - ( ( ( ( ( keyRowOne ) - holderStemY ) - 1.2 mm ) * cos(caseTilt) + ( holderBottomDepth + holderLidGap ) * sin(caseTilt) ) - 1.5 mm )"
equation "d1950 = ( frontHeight + ( ( ( keyRowOne ) - holderStemY ) - 1.2 mm ) * sin(caseTilt) - ( holderBottomDepth + holderLidGap ) * cos(caseTilt) ) - bottomThickness + 0.5 mm"
equation "d1952 = ( ( ( layoutGap + keycapSize / 2 + 0 * keyPitch ) - holderStemX ) + ( -2.5 mm ) - 0.5 mm ) - 0.1 mm"
equation "d1953 = ( ( ( ( keyRowOne ) - holderStemY ) - 1.2 mm ) - 2 mm ) + faceOriginV"
equation "d1954 = ( ( ( ( ( layoutGap + keycapSize / 2 + 0 * keyPitch ) - holderStemX ) + ( -2.5 mm ) - 0.5 mm ) - 0.1 mm ) + ( 1.2 mm ) ) - ( ( ( ( layoutGap + keycapSize / 2 + 0 * keyPitch ) - holderStemX ) + ( -2.5 mm ) - 0.5 mm ) - 0.1 mm )"
equation "d1955 = ( ( ( ( ( ( keyRowOne ) - holderStemY ) - 1.2 mm ) - 2 mm ) + faceOriginV ) + ( 4 mm ) ) - ( ( ( ( ( keyRowOne ) - holderStemY ) - 1.2 mm ) - 2 mm ) + faceOriginV )"
equation "d1956 = rearHeight"
equation "d1958 = ( ( layoutGap + keycapSize / 2 + 0 * keyPitch ) - holderStemX ) + ( 2.5 mm ) - 1.2 mm"
equation "d1959 = ( ( ( ( keyRowOne ) - holderStemY ) - 1.2 mm ) * cos(caseTilt) + ( holderBottomDepth + holderLidGap ) * sin(caseTilt) ) - 2.5 mm"
equation "d1960 = ( ( ( ( layoutGap + keycapSize / 2 + 0 * keyPitch ) - holderStemX ) + ( 2.5 mm ) - 1.2 mm ) + ( 2.4 mm ) ) - ( ( ( layoutGap + keycapSize / 2 + 0 * keyPitch ) - holderStemX ) + ( 2.5 mm ) - 1.2 mm )"
equation "d1961 = ( ( ( ( ( ( keyRowOne ) - holderStemY ) - 1.2 mm ) * cos(caseTilt) + ( holderBottomDepth + holderLidGap ) * sin(caseTilt) ) - 2.5 mm ) + ( 5 mm ) ) - ( ( ( ( ( keyRowOne ) - holderStemY ) - 1.2 mm ) * cos(caseTilt) + ( holderBottomDepth + holderLidGap ) * sin(caseTilt) ) - 2.5 mm )"
equation "d1962 = ( frontHeight + ( ( ( keyRowOne ) - holderStemY ) - 1.2 mm ) * sin(caseTilt) - ( holderBottomDepth + holderLidGap ) * cos(caseTilt) ) - bottomThickness - 2 mm"
equation "d1964 = ( ( layoutGap + keycapSize / 2 + 0 * keyPitch ) - holderStemX ) + ( 2.5 mm ) - 0.5 mm"
equation "d1965 = ( ( ( ( keyRowOne ) - holderStemY ) - 1.2 mm ) * cos(caseTilt) + ( holderBottomDepth + holderLidGap ) * sin(caseTilt) ) - 1.5 mm"
equation "d1966 = ( ( ( ( layoutGap + keycapSize / 2 + 0 * keyPitch ) - holderStemX ) + ( 2.5 mm ) - 0.5 mm ) + ( 1 mm ) ) - ( ( ( layoutGap + keycapSize / 2 + 0 * keyPitch ) - holderStemX ) + ( 2.5 mm ) - 0.5 mm )"
equation "d1967 = ( ( ( ( ( ( keyRowOne ) - holderStemY ) - 1.2 mm ) * cos(caseTilt) + ( holderBottomDepth + holderLidGap ) * sin(caseTilt) ) - 1.5 mm ) + ( 3 mm ) ) - ( ( ( ( ( keyRowOne ) - holderStemY ) - 1.2 mm ) * cos(caseTilt) + ( holderBottomDepth + holderLidGap ) * sin(caseTilt) ) - 1.5 mm )"
equation "d1968 = ( frontHeight + ( ( ( keyRowOne ) - holderStemY ) - 1.2 mm ) * sin(caseTilt) - ( holderBottomDepth + holderLidGap ) * cos(caseTilt) ) - bottomThickness + 0.5 mm"
equation "d1970 = ( ( ( layoutGap + keycapSize / 2 + 0 * keyPitch ) - holderStemX ) + ( 2.5 mm ) - 0.5 mm ) - 0.1 mm"
equation "d1971 = ( ( ( ( keyRowOne ) - holderStemY ) - 1.2 mm ) - 2 mm ) + faceOriginV"
equation "d1972 = ( ( ( ( ( layoutGap + keycapSize / 2 + 0 * keyPitch ) - holderStemX ) + ( 2.5 mm ) - 0.5 mm ) - 0.1 mm ) + ( 1.2 mm ) ) - ( ( ( ( layoutGap + keycapSize / 2 + 0 * keyPitch ) - holderStemX ) + ( 2.5 mm ) - 0.5 mm ) - 0.1 mm )"
equation "d1973 = ( ( ( ( ( ( keyRowOne ) - holderStemY ) - 1.2 mm ) - 2 mm ) + faceOriginV ) + ( 4 mm ) ) - ( ( ( ( ( keyRowOne ) - holderStemY ) - 1.2 mm ) - 2 mm ) + faceOriginV )"
equation "d1974 = rearHeight"
equation "d1976 = ( layoutGap + keycapSize / 2 + 1 * keyPitch ) - holderFrameX / 2"
equation "d1977 = ( ( keyRowOne ) - holderFrameY / 2 ) + faceOriginV"
equation "d1978 = ( ( ( layoutGap + keycapSize / 2 + 1 * keyPitch ) - holderFrameX / 2 ) + ( holderFrameX ) ) - ( ( layoutGap + keycapSize / 2 + 1 * keyPitch ) - holderFrameX / 2 )"
equation "d1979 = ( ( ( ( keyRowOne ) - holderFrameY / 2 ) + faceOriginV ) + ( holderFrameY ) ) - ( ( ( keyRowOne ) - holderFrameY / 2 ) + faceOriginV )"
equation "d1980 = -( holderBottomDepth + holderHookThickness - shellWall - carrierClearance - carrierThickness )"
equation "d1982 = ( layoutGap + keycapSize / 2 + 1 * keyPitch ) - holderSwitchVoid / 2"
equation "d1983 = ( ( keyRowOne ) - holderSwitchVoid / 2 ) + faceOriginV"
equation "d1984 = ( ( ( layoutGap + keycapSize / 2 + 1 * keyPitch ) - holderSwitchVoid / 2 ) + ( holderSwitchVoid ) ) - ( ( layoutGap + keycapSize / 2 + 1 * keyPitch ) - holderSwitchVoid / 2 )"
equation "d1985 = ( ( ( ( keyRowOne ) - holderSwitchVoid / 2 ) + faceOriginV ) + ( holderSwitchVoid ) ) - ( ( ( keyRowOne ) - holderSwitchVoid / 2 ) + faceOriginV )"
equation "d1986 = -( holderTopDepth - shellWall - carrierClearance - carrierThickness )"
equation "d1988 = ( ( layoutGap + keycapSize / 2 + 1 * keyPitch ) - holderStemX ) - holderWidth / 2 - holderFit"
equation "d1989 = ( ( ( keyRowOne ) - holderStemY ) - holderLength / 2 - holderFit ) + faceOriginV"
equation "d1990 = ( ( ( ( layoutGap + keycapSize / 2 + 1 * keyPitch ) - holderStemX ) - holderWidth / 2 - holderFit ) + ( holderWidth + 2 * holderFit ) ) - ( ( ( layoutGap + keycapSize / 2 + 1 * keyPitch ) - holderStemX ) - holderWidth / 2 - holderFit )"
equation "d1991 = ( ( ( ( ( keyRowOne ) - holderStemY ) - holderLength / 2 - holderFit ) + faceOriginV ) + ( holderLength + 2 * holderFit ) ) - ( ( ( ( keyRowOne ) - holderStemY ) - holderLength / 2 - holderFit ) + faceOriginV )"
equation "d1992 = -( holderHeight + holderHookThickness + 0.2 mm )"
equation "d1994 = ( ( layoutGap + keycapSize / 2 + 1 * keyPitch ) - holderStemX ) - holderFrameX / 2 - 0.1 mm"
equation "d1995 = ( ( ( ( keyRowOne ) - holderStemY ) + holderSpringY ) - holderSpringWidth / 2 - 0.6 mm ) + faceOriginV"
equation "d1996 = ( ( ( ( layoutGap + keycapSize / 2 + 1 * keyPitch ) - holderStemX ) - holderFrameX / 2 - 0.1 mm ) + ( holderFrameX / 2 - holderWidth / 2 - holderFit + 0.1 mm ) ) - ( ( ( layoutGap + keycapSize / 2 + 1 * keyPitch ) - holderStemX ) - holderFrameX / 2 - 0.1 mm )"
equation "d1997 = ( ( ( ( ( ( keyRowOne ) - holderStemY ) + holderSpringY ) - holderSpringWidth / 2 - 0.6 mm ) + faceOriginV ) + ( 0.6 mm ) ) - ( ( ( ( ( keyRowOne ) - holderStemY ) + holderSpringY ) - holderSpringWidth / 2 - 0.6 mm ) + faceOriginV )"
equation "d1998 = -( holderBottomDepth + holderHookThickness - shellWall - carrierClearance - carrierThickness - 1 mm + 0.2 mm )"
equation "d2000 = ( ( layoutGap + keycapSize / 2 + 1 * keyPitch ) - holderStemX ) - holderFrameX / 2 - 0.1 mm"
equation "d2001 = ( ( ( ( keyRowOne ) - holderStemY ) + holderSpringY ) + holderSpringWidth / 2 ) + faceOriginV"
equation "d2002 = ( ( ( ( layoutGap + keycapSize / 2 + 1 * keyPitch ) - holderStemX ) - holderFrameX / 2 - 0.1 mm ) + ( holderFrameX / 2 - holderWidth / 2 - holderFit + 0.1 mm ) ) - ( ( ( layoutGap + keycapSize / 2 + 1 * keyPitch ) - holderStemX ) - holderFrameX / 2 - 0.1 mm )"
equation "d2003 = ( ( ( ( ( ( keyRowOne ) - holderStemY ) + holderSpringY ) + holderSpringWidth / 2 ) + faceOriginV ) + ( 0.6 mm ) ) - ( ( ( ( ( keyRowOne ) - holderStemY ) + holderSpringY ) + holderSpringWidth / 2 ) + faceOriginV )"
equation "d2004 = -( holderBottomDepth + holderHookThickness - shellWall - carrierClearance - carrierThickness - 1 mm + 0.2 mm )"
equation "d2006 = ( ( layoutGap + keycapSize / 2 + 1 * keyPitch ) - holderStemX ) - holderFrameX / 2 + 0.8 mm"
equation "d2007 = ( ( ( ( keyRowOne ) - holderStemY ) + holderSpringY ) - holderSpringWidth / 2 ) + faceOriginV"
equation "d2008 = ( ( ( ( layoutGap + keycapSize / 2 + 1 * keyPitch ) - holderStemX ) - holderFrameX / 2 + 0.8 mm ) + ( holderFrameX / 2 - 0.8 mm - holderWidth / 2 - holderFit ) ) - ( ( ( layoutGap + keycapSize / 2 + 1 * keyPitch ) - holderStemX ) - holderFrameX / 2 + 0.8 mm )"
equation "d2009 = ( ( ( ( ( ( keyRowOne ) - holderStemY ) + holderSpringY ) - holderSpringWidth / 2 ) + faceOriginV ) + ( holderSpringWidth ) ) - ( ( ( ( ( keyRowOne ) - holderStemY ) + holderSpringY ) - holderSpringWidth / 2 ) + faceOriginV )"
equation "d2010 = -( holderHeight + holderHookThickness + 0.2 mm )"
equation "d2012 = ( ( layoutGap + keycapSize / 2 + 1 * keyPitch ) - holderStemX ) - holderFrameX / 2"
equation "d2013 = ( ( ( ( keyRowOne ) - holderStemY ) + holderSpringY ) - holderSpringWidth / 2 ) + faceOriginV"
equation "d2014 = ( ( ( ( layoutGap + keycapSize / 2 + 1 * keyPitch ) - holderStemX ) - holderFrameX / 2 ) + ( holderFrameX / 2 - holderWidth / 2 + holderHookOverlap ) ) - ( ( ( layoutGap + keycapSize / 2 + 1 * keyPitch ) - holderStemX ) - holderFrameX / 2 )"
equation "d2015 = ( ( ( ( ( ( keyRowOne ) - holderStemY ) + holderSpringY ) - holderSpringWidth / 2 ) + faceOriginV ) + ( holderSpringWidth ) ) - ( ( ( ( ( keyRowOne ) - holderStemY ) + holderSpringY ) - holderSpringWidth / 2 ) + faceOriginV )"
equation "d2016 = -( holderHookThickness )"
equation "d2019 = ( ( layoutGap + keycapSize / 2 + 1 * keyPitch ) - holderStemX ) + holderWidth / 2 + holderFit"
equation "d2020 = ( ( ( ( keyRowOne ) - holderStemY ) + holderSpringY ) - holderSpringWidth / 2 - 0.6 mm ) + faceOriginV"
equation "d2021 = ( ( ( ( layoutGap + keycapSize / 2 + 1 * keyPitch ) - holderStemX ) + holderWidth / 2 + holderFit ) + ( holderFrameX / 2 - holderWidth / 2 - holderFit + 0.1 mm ) ) - ( ( ( layoutGap + keycapSize / 2 + 1 * keyPitch ) - holderStemX ) + holderWidth / 2 + holderFit )"
equation "d2022 = ( ( ( ( ( ( keyRowOne ) - holderStemY ) + holderSpringY ) - holderSpringWidth / 2 - 0.6 mm ) + faceOriginV ) + ( 0.6 mm ) ) - ( ( ( ( ( keyRowOne ) - holderStemY ) + holderSpringY ) - holderSpringWidth / 2 - 0.6 mm ) + faceOriginV )"
equation "d2023 = -( holderBottomDepth + holderHookThickness - shellWall - carrierClearance - carrierThickness - 1 mm + 0.2 mm )"
equation "d2025 = ( ( layoutGap + keycapSize / 2 + 1 * keyPitch ) - holderStemX ) + holderWidth / 2 + holderFit"
equation "d2026 = ( ( ( ( keyRowOne ) - holderStemY ) + holderSpringY ) + holderSpringWidth / 2 ) + faceOriginV"
equation "d2027 = ( ( ( ( layoutGap + keycapSize / 2 + 1 * keyPitch ) - holderStemX ) + holderWidth / 2 + holderFit ) + ( holderFrameX / 2 - holderWidth / 2 - holderFit + 0.1 mm ) ) - ( ( ( layoutGap + keycapSize / 2 + 1 * keyPitch ) - holderStemX ) + holderWidth / 2 + holderFit )"
equation "d2028 = ( ( ( ( ( ( keyRowOne ) - holderStemY ) + holderSpringY ) + holderSpringWidth / 2 ) + faceOriginV ) + ( 0.6 mm ) ) - ( ( ( ( ( keyRowOne ) - holderStemY ) + holderSpringY ) + holderSpringWidth / 2 ) + faceOriginV )"
equation "d2029 = -( holderBottomDepth + holderHookThickness - shellWall - carrierClearance - carrierThickness - 1 mm + 0.2 mm )"
equation "d2031 = ( ( layoutGap + keycapSize / 2 + 1 * keyPitch ) - holderStemX ) + holderWidth / 2 + holderFit"
equation "d2032 = ( ( ( ( keyRowOne ) - holderStemY ) + holderSpringY ) - holderSpringWidth / 2 ) + faceOriginV"
equation "d2033 = ( ( ( ( layoutGap + keycapSize / 2 + 1 * keyPitch ) - holderStemX ) + holderWidth / 2 + holderFit ) + ( holderFrameX / 2 - 0.8 mm - holderWidth / 2 - holderFit ) ) - ( ( ( layoutGap + keycapSize / 2 + 1 * keyPitch ) - holderStemX ) + holderWidth / 2 + holderFit )"
equation "d2034 = ( ( ( ( ( ( keyRowOne ) - holderStemY ) + holderSpringY ) - holderSpringWidth / 2 ) + faceOriginV ) + ( holderSpringWidth ) ) - ( ( ( ( ( keyRowOne ) - holderStemY ) + holderSpringY ) - holderSpringWidth / 2 ) + faceOriginV )"
equation "d2035 = -( holderHeight + holderHookThickness + 0.2 mm )"
equation "d2037 = ( ( layoutGap + keycapSize / 2 + 1 * keyPitch ) - holderStemX ) + holderWidth / 2 - holderHookOverlap"
equation "d2038 = ( ( ( ( keyRowOne ) - holderStemY ) + holderSpringY ) - holderSpringWidth / 2 ) + faceOriginV"
equation "d2039 = ( ( ( ( layoutGap + keycapSize / 2 + 1 * keyPitch ) - holderStemX ) + holderWidth / 2 - holderHookOverlap ) + ( holderFrameX / 2 - holderWidth / 2 + holderHookOverlap ) ) - ( ( ( layoutGap + keycapSize / 2 + 1 * keyPitch ) - holderStemX ) + holderWidth / 2 - holderHookOverlap )"
equation "d2040 = ( ( ( ( ( ( keyRowOne ) - holderStemY ) + holderSpringY ) - holderSpringWidth / 2 ) + faceOriginV ) + ( holderSpringWidth ) ) - ( ( ( ( ( keyRowOne ) - holderStemY ) + holderSpringY ) - holderSpringWidth / 2 ) + faceOriginV )"
equation "d2041 = -( holderHookThickness )"
equation "d2044 = ( ( layoutGap + keycapSize / 2 + 1 * keyPitch ) - holderStemX ) + ( -3 mm ) - 0.5 mm"
equation "d2045 = ( ( ( keyRowOne ) - holderStemY ) + 4 mm ) + faceOriginV"
equation "d2046 = ( ( ( ( layoutGap + keycapSize / 2 + 1 * keyPitch ) - holderStemX ) + ( -3 mm ) - 0.5 mm ) + ( 1 mm ) ) - ( ( ( layoutGap + keycapSize / 2 + 1 * keyPitch ) - holderStemX ) + ( -3 mm ) - 0.5 mm )"
equation "d2047 = ( ( ( ( ( keyRowOne ) - holderStemY ) + 4 mm ) + faceOriginV ) + ( holderFrameY / 2 - 4 mm ) ) - ( ( ( ( keyRowOne ) - holderStemY ) + 4 mm ) + faceOriginV )"